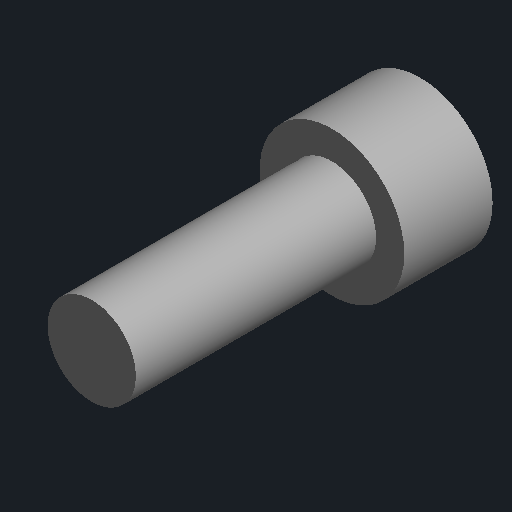
# Autodesk Inventor part: nas1352n06_6
Saved by Autodesk Inventor 2027.1 (Build 311270010, 270A)
## iProperties
Part Number: nas1352n06_6
Material: Generic
Document SubType Name: Modeling
Designer: User
Appearance: Steel - Polished
Author: User
Autodesk Inventor part; units mm, degrees
ref_plane "YZ Plane" through (0, 0, 0) normal (1, 0, 0) x (0, 1, 0)
ref_plane "XZ Plane" through (0, 0, 0) normal (0, 1, 0) x (-1, 0, 0)
ref_plane "XY Plane" through (0, 0, 0) normal (0, 0, 1) x (1, 0, 0)
sketch "Sketch1" plane through (0, 0, 0) normal (0, 0, 1) x (1, 0, 0)
  circle A0 centre (0, 0) radius 1.7526
  constraints: 1 centre point
extrude "Extrusion1" add sketch "Sketch1" along normal blind 9.525
sketch "Sketch2" plane through (0, 0, 0) normal (0, 0, 1) x (1, 0, 0)
  circle A0 centre (0, 0) radius 2.8702
  constraints: 1 centre point
extrude "Extrusion2" add sketch "Sketch2" against normal blind 3.5052
body "Solid1"
